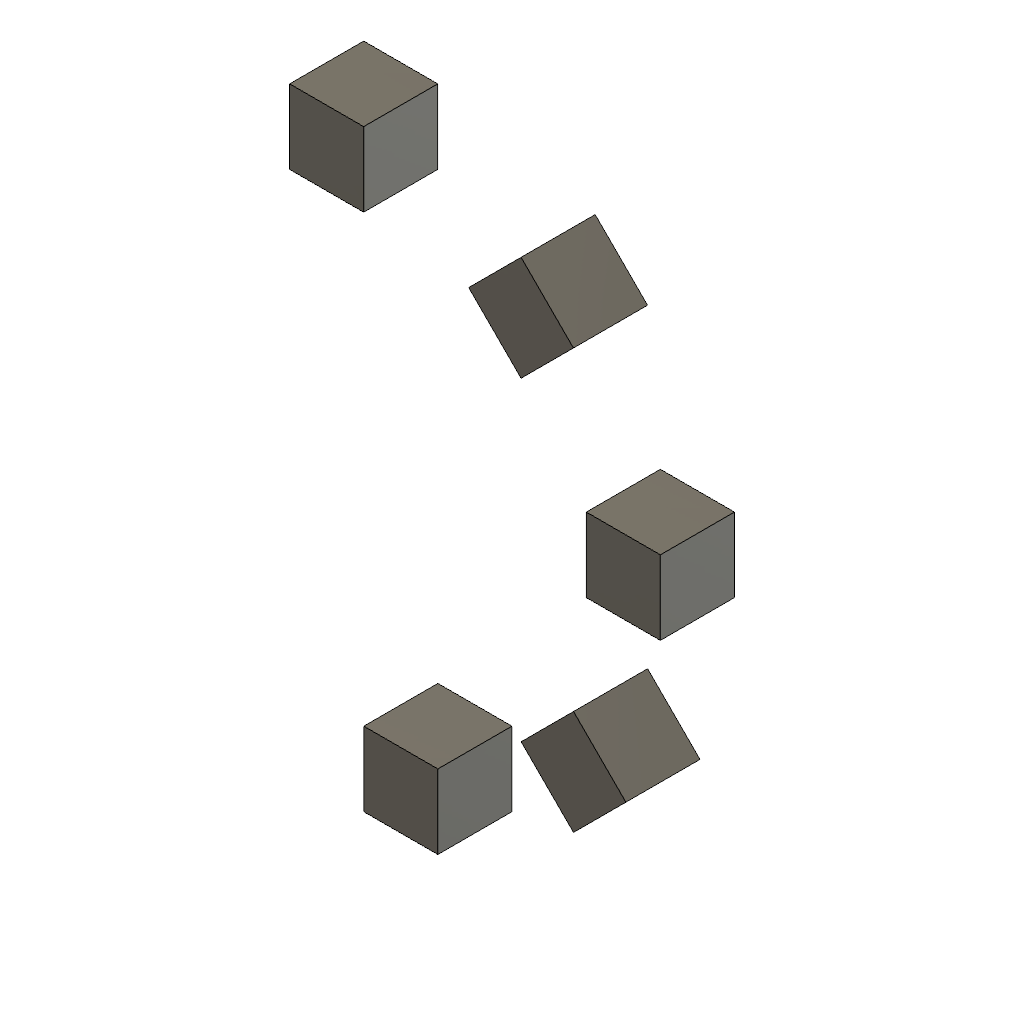
body_symmetric (Autodesk Fusion 360 design; units mm, degrees)
part number: 2026-10-20-21-04-42-707
Autodesk Fusion 360 part; units mm, degrees
sketch "Sketch1" plane through (0, 0, 0) normal (0, 0, 1) x (1, 0, 0)
  line L0 (30, 0) -> (40, 0)
  line L1 (40, 0) -> (40, 10)
  line L2 (40, 10) -> (30, 10)
  line L3 (30, 10) -> (30, 0)
extrude "SeedFeature0" add sketch "Sketch1" along normal blind 10 makes body 1
pattern_circular "ProbeCircularPattern" count 5 over 180 about axis through (0, 0, 1.75) along (0, 0, 1) both ways of bodies 1 makes body 2 at (6.6667, -30, 3.3333) makes body 3 at (25.9272, -16.4992, 3.3333) makes body 4 at (18.8562, 32.9983, 3.3333) makes body 5 at (-6.6667, 30, 3.3333)
named bodies: "SeedBody0", "SeedBody0 (1)", "SeedBody0 (2)", "SeedBody0 (3)", "SeedBody0 (4)"
